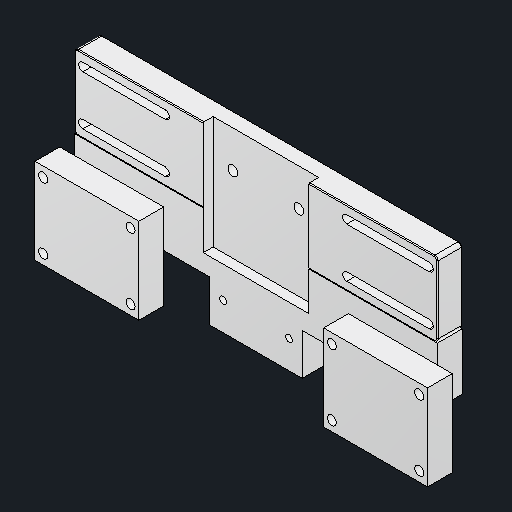
# Autodesk Inventor part: monotaro-rear-drive-foot
Saved by Autodesk Inventor 2027.1 (Build 311270010, 270A)
## iProperties
Created: 2026-10-07
Part Number: monotaro-rear-drive-foot
Material: Aluminum 6061
Document SubType Name: Modeling
Designer: queezz
Density: 2.7 g/cm^3
Appearance: Aluminum - Flat
Author: queezz
Autodesk Inventor part; units mm, degrees
sketch "Sketch1" plane through (0, 0, 0) normal (0, 0, 1) x (1, 0, 0)
  line L0 (-110, 22.5) -> (110, 22.5)
  line L1 (110, 22.5) -> (110, -22.5)
  line L2 (110, -22.5) -> (-110, -22.5)
  line L3 (-110, -22.5) -> (-110, 22.5)
  point P0 (0, 0)
  point P1 (110, 0)
  point P2 (0, 22.5)
  dimension "d0" = 220
  dimension "d1" = 45
  constraints: 8 end point, 2 midpoint, 2 parallel, 1 horizontal, 1 horizontal alignment, 1 perpendicular, 1 vertical alignment
  measures "d0" distance of L0.start L0.end
  measures "d1" distance of L0.end L1.end
extrude "Extrusion1" add sketch "Sketch1" along normal blind 15
sketch "Sketch2" plane through (0, 0, 15) normal (0, 0, 1) x (1, 0, 0)
  line L0 (-105, 15) -> (-55, 15) construction
  line L1 (-105, 12.5) -> (-55, 12.5)
  line L2 (-55, 17.5) -> (-105, 17.5)
  arc A0 (-105, 17.5) -> (-105, 12.5) centre (-105, 15) ccw
  arc A1 (-55, 12.5) -> (-55, 17.5) centre (-55, 15) ccw
  line L3 (-105, -15) -> (-55, -15) construction
  line L4 (-105, -17.5) -> (-55, -17.5)
  line L5 (-55, -12.5) -> (-105, -12.5)
  arc A2 (-105, -12.5) -> (-105, -17.5) centre (-105, -15) ccw
  arc A3 (-55, -17.5) -> (-55, -12.5) centre (-55, -15) ccw
  line L6 (-80, 15) -> (-80, -15) construction
  line L7 (-110, 22.5) -> (-110, -22.5) projected
  point P0 (0, 0)
  point P1 (-80, 0)
  dimension "d4" = 5
  dimension "d5" = 30
  dimension "d6" = 50
  dimension "d7" = 5
  constraints: 18 end point, 8 point on circle, 8 tangent, 4 centre point, 4 parallel, 3 midpoint, 1 equal radius, 1 horizontal, 1 horizontal alignment, 1 vertical
  measures "d4" diameter of A1
  measures "d5" distance between parallel lines of L3 L0
  measures "d6" distance of L2.start L2.end
  measures "d7" distance from line of L7 L0.start
extrude "Extrusion2" cut sketch "Sketch2" against normal through all
mirror "Mirror1" about plane through (0, 0, 0) normal (1, 0, 0) of "Extrusion2"
fillet "Fillet1" radius 2 4 edges at (-110, -22.5, 7.5) (-110, 22.5, 7.5) (110, 22.5, 7.5) (110, -22.5, 7.5)
chamfer "Chamfer1" distance 0.5 angle 45 16 edges at (0, 22.5, 15) (-109.4142, 21.9142, 15) (-110, 0, 15) (-109.4142, -21.9142, 15) (0, -22.5, 15) (109.4142, -21.9142, 15) (110, 0, 15) (109.4142, 21.9142, 15) (0, -22.5, 0) (109.4142, -21.9142, 0) (110, 0, 0) (109.4142, 21.9142, 0) (0, 22.5, 0) (-109.4142, 21.9142, 0) (-110, 0, 0) (-109.4142, -21.9142, 0)
sketch "Sketch3" plane through (0, 0, 15) normal (0, 0, -1) x (-1, 0, 0)
  line L0 (-20, 0) -> (20, 0) construction
  point P0 (0, 0)
  point P1 (0, 0)
  dimension "d14" = 40
  constraints: 3 coincident, 2 end point, 1 horizontal, 1 midpoint
  measures "d14" distance of L0.start L0.end
hole "Hole1" at (20, 0, 15) at (-20, 0, 15) direction (0, 0, -1) diameter 6 end through all counterbore diameter 12 counterbore depth 5
ref_plane "M5 MonotaRO adapter interface layout plane" through (0, 0, 15) normal (0, 0, 1) x (1, 0, 0)
sketch "M5 MonotaRO adapter interface layout" plane through (0, 0, 15) normal (0, 0, 1) x (1, 0, 0)
  circle A0 centre (-63.5, -15) radius 2.75
  circle A1 centre (-63.5, 15) radius 2.75
  circle A2 centre (63.5, -15) radius 2.75
  circle A3 centre (63.5, 15) radius 2.75
  constraints: 4 centre point
extrude "M5 MonotaRO adapter interface" [suppressed]
ref_plane "Work Plane2" through (0, 0, 15) normal (0, 0, 1) x (1, 0, 0)
sketch "Integral guide pads" plane through (0, 0, 15) normal (0, 0, 1) x (1, 0, 0)
  line L0 (-119, -26) -> (-56, -26)
  line L1 (-56, -26) -> (-56, 26)
  line L2 (-56, 26) -> (-119, 26)
  line L3 (-119, 26) -> (-119, -26)
  line L4 (56, -26) -> (119, -26)
  line L5 (119, -26) -> (119, 26)
  line L6 (119, 26) -> (56, 26)
  line L7 (56, 26) -> (56, -26)
  constraints: 16 end point, 4 parallel, 2 horizontal, 2 perpendicular
extrude "Integral 15 mm guide pads" [suppressed]
ref_plane "Work Plane3" through (0, 0, 30) normal (0, 0, 1) x (1, 0, 0)
sketch "SBI20FL M5 clearance, 53 x 40" plane through (0, 0, 30) normal (0, 0, 1) x (1, 0, 0)
  circle A0 centre (-114, -20) radius 2.75
  circle A1 centre (-114, 20) radius 2.75
  circle A2 centre (-61, -20) radius 2.75
  circle A3 centre (-61, 20) radius 2.75
  circle A4 centre (61, -20) radius 2.75
  circle A5 centre (61, 20) radius 2.75
  circle A6 centre (114, -20) radius 2.75
  circle A7 centre (114, 20) radius 2.75
  constraints: 8 centre point
extrude "SBI20FL through clearances" [suppressed]
ref_plane "Work Plane4" through (0, 0, 0) normal (0, 0, 1) x (1, 0, 0)
sketch "Rear inboard foot extension" plane through (0, 0, 0) normal (0, 0, 1) x (1, 0, 0)
  line L0 (-110, -56.8) -> (110, -56.8)
  line L1 (110, -56.8) -> (110, -22.5)
  line L2 (110, -22.5) -> (-110, -22.5)
  line L3 (-110, -22.5) -> (-110, -56.8)
  constraints: 8 end point, 2 parallel, 1 horizontal, 1 perpendicular
extrude "Rear foot bridge" add sketch "Rear inboard foot extension" along normal blind 15
ref_plane "Work Plane5" through (0, 0, 15) normal (0, 0, 1) x (1, 0, 0)
sketch "Rear guide pads 60 mm inboard" plane through (0, 0, 15) normal (0, 0, 1) x (1, 0, 0)
  line L0 (-119, -86) -> (-56, -86)
  line L1 (-56, -86) -> (-56, -34)
  line L2 (-56, -34) -> (-119, -34)
  line L3 (-119, -34) -> (-119, -86)
  line L4 (56, -86) -> (119, -86)
  line L5 (119, -86) -> (119, -34)
  line L6 (119, -34) -> (56, -34)
  line L7 (56, -34) -> (56, -86)
  constraints: 16 end point, 4 parallel, 2 horizontal, 2 perpendicular
extrude "Integral rear guide pads" add sketch "Rear guide pads 60 mm inboard" along normal blind 15
ref_plane "Work Plane6" through (0, 0, 30) normal (0, 0, 1) x (1, 0, 0)
sketch "Rear SBI20FL clearance pattern" plane through (0, 0, 30) normal (0, 0, 1) x (1, 0, 0)
  circle A0 centre (-114, -80) radius 2.75
  circle A1 centre (-114, -40) radius 2.75
  circle A2 centre (-61, -80) radius 2.75
  circle A3 centre (-61, -40) radius 2.75
  circle A4 centre (61, -80) radius 2.75
  circle A5 centre (61, -40) radius 2.75
  circle A6 centre (114, -80) radius 2.75
  circle A7 centre (114, -40) radius 2.75
  constraints: 8 centre point
extrude "Rear guide clearances" cut sketch "Rear SBI20FL clearance pattern" against normal blind 30
ref_plane "Work Plane7" through (0, 0, 15) normal (0, 0, 1) x (1, 0, 0)
sketch "Wheel end support passage" plane through (0, 0, 15) normal (0, 0, 1) x (1, 0, 0)
  line L0 (-32, -46) -> (32, -46)
  line L1 (32, -46) -> (32, 24)
  line L2 (32, 24) -> (-32, 24)
  line L3 (-32, 24) -> (-32, -46)
  constraints: 8 end point, 2 parallel, 1 horizontal, 1 perpendicular
extrude "Wheel support underside relief" cut sketch "Wheel end support passage" against normal blind 6
ref_plane "Work Plane8" through (0, 0, 15) normal (0, 0, 1) x (1, 0, 0)
sketch "TR16 housing screw pilots" plane through (0, 0, 15) normal (0, 0, 1) x (1, 0, 0)
  circle A0 centre (-20, -65) radius 2.1
  circle A1 centre (20, -65) radius 2.1
  constraints: 2 centre point
extrude "Two M5 housing tap pilots" [suppressed]
ref_plane "Work Plane9" through (0, 0, 15) normal (0, 0, 1) x (1, 0, 0)
sketch "M5 nut housing pattern at 40 mm centers" plane through (0, 0, 15) normal (0, 0, 1) x (1, 0, 0)
  circle A0 centre (-20, -65) radius 2.1
  circle A1 centre (20, -65) radius 2.1
  constraints: 2 centre point
extrude "M5 housing pilot holes into rear foot" [suppressed]
ref_plane "Work Plane10" through (0, 0, 15.1) normal (0, 0, 1) x (1, 0, 0)
sketch "Sketch13" plane through (0, 0, 15.1) normal (0, 0, 1) x (1, 0, 0)
  circle A0 centre (-20, -65) radius 2.1
  circle A1 centre (20, -65) radius 2.1
  constraints: 2 centre point
extrude "Fixed datum M5 tap pilots" [suppressed]
sketch "Sketch14" plane through (0, 0, 0) normal (0, 0, 1) x (1, 0, 0)
  line L0 (-28, -82) -> (28, -82)
  line L1 (28, -82) -> (28, -52)
  line L2 (28, -52) -> (-28, -52)
  line L3 (-28, -52) -> (-28, -82)
  constraints: 8 end point, 2 parallel, 1 horizontal, 1 perpendicular
extrude "Nut mounting bridge extension" add sketch "Sketch14" along normal blind 15
ref_plane "Work Plane11" through (0, 0, 15.1) normal (0, 0, 1) x (1, 0, 0)
sketch "Rear nut mount pilot layout" plane through (0, 0, 15.1) normal (0, 0, 1) x (1, 0, 0)
  circle A0 centre (-20, -65) radius 2.1
  circle A1 centre (20, -65) radius 2.1
  constraints: 2 centre point
extrude "Rear nut mount M5 pilots" cut sketch "Rear nut mount pilot layout" against normal blind 11.6
body "Solid1"
